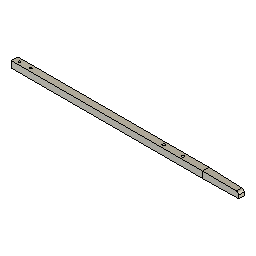
Assembly (Autodesk Fusion 360 archive; units mm, degrees)
design "Solid fuselage"
Autodesk Fusion 360 part; units mm, degrees
sketch "Profile" plane through (0, 0, 0) normal (1, 0, 0) x (0, 1, 0)
  line L0 (10, -10) -> (-10, -10)
  line L1 (-10, -10) -> (-10, 10)
  line L2 (-10, 10) -> (10, 10)
  line L3 (10, 10) -> (10, -10)
  line L4 (10, -10) -> (-10, 10) construction
  line L5 (-10, -10) -> (10, 10) construction
  dimension "d1" = 20
  dimension "d2" = 20
  constraint horizontal L0
  constraint perpendicular L0 L1
  constraint parallel L0 L2
  constraint parallel L1 L3
  constraint coincident L4 origin
  constraint coincident L5 origin
  measures "d1" distance of L0.end L1.end
  measures "d2" distance of L1.end L2.end
extrude "Extrude1" add sketch "Profile" along normal mid plane 700 makes body 1
sketch "Bottom" plane through (0, 0, -10) normal (0, 0, -1) x (1, 0, 0)
  line L0 (-350, -10) -> (350, -10)
  line L1 (350, -10) -> (350, 10)
  line L2 (350, 10) -> (-350, 10)
  line L3 (-350, 10) -> (-350, -10)
  line L4 (350, 0) -> (-28.4363, 0) construction
  circle A0 centre (245, 0) radius 3
  circle A1 centre (290, 0) radius 3
  circle A2 centre (335, 0) radius 3
  circle A3 centre (170, 0) radius 4
  circle A4 centre (110, 0) radius 4
  dimension "d5" = 6
  dimension "d6" = 15
  dimension "d7" = 45
  dimension "d8" = 45
  dimension "d35" = 8
  dimension "d36" = 8
  dimension "d37" = 60
  dimension "d38" = 180
  constraint midpoint L1 L4.start
  constraint perpendicular L1 L4
  constraint coincident L4 A0.centre
  constraint coincident L4 A2.centre
  constraint equal A1 A2
  constraint equal A0 A2
  constraint coincident L4 A1.centre
  constraint coincident L4 A3.centre
  constraint coincident L4 A4.centre
  measures "d5" diameter of A2
  measures "d6" distance of L1 A2.centre
  measures "d7" distance of A1.centre A2.centre
  measures "d8" distance of A0.centre A1.centre
  measures "d35" diameter of A3
  measures "d36" diameter of A4
  measures "d37" distance of A3.centre A4.centre
  measures "d38" distance of L1 A3.centre
sketch "Draft B" plane through (0, 0, -10) normal (0, 0, -1) x (1, 0, 0)
  line L0 (-350, -10) -> (350, -10)
  line L1 (350, -10) -> (350, 10)
  line L2 (350, 10) -> (-350, 10)
  line L3 (-350, 10) -> (-350, -10)
  line L4 (240, 10) -> (350, 8.25)
  line L5 (1.75, 0) -> (22.5, 0)
  line L6 (240, -10) -> (350, -8.25)
  line L7 (350, 0) -> (-28.4363, 0)
  line L8 (350, 8.25) -> (350, -8.25)
  dimension "d13" = 110
  dimension "d77" = 16.5
  constraint coincident L2 L4.start
  constraint coincident L1 L4.end
  constraint symmetric L4.start L5 L6.start
  constraint symmetric L4.end L5 L6.end
  constraint vertical L8
  constraint midpoint L7.start L8
  constraint coincident L4.end L8.start
  measures "d13" distance of L1.end L4.start
  measures "d77" distance of L6.end L4.end
sketch "Draft S" plane through (0, -10, 0) normal (0, -1, 0) x (1, 0, 0)
  line L0 (-350, -10) -> (350, -10)
  line L1 (350, -10) -> (350, 10)
  line L2 (350, 10) -> (-350, 10)
  line L3 (-350, 10) -> (-350, -10)
  line L4 (240, 10) -> (350, 7)
  line L5 (1.75, 0) -> (22.5, 0) construction
  line L6 (350, -10) -> (350, 7)
  dimension "d15" = 110
  dimension "d78" = 17
  constraint coincident L2 L4.start
  constraint coincident L1 L4.end
  constraint coincident L0.end L1.start
  constraint parallel L1 L6
  measures "d15" distance of L1.end L4.start
  measures "d78" distance of L4.end L0.end
extrude "Extrude2" cut sketch "Draft S" against normal through all contours L1 L2 L4 bodies 1
extrude "Extrude3" cut sketch "Draft B" against normal through all contours L0 L1 L6 | L1 L2 L4 bodies 1
sketch "Rear Wing" plane through (0, 0, 10) normal (0, 0, 1) x (-1, 0, 0)
  line L0 (-240, 10) -> (-240, -10)
  line L1 (-240, -10) -> (350, -10)
  line L2 (350, -10) -> (350, 10)
  line L3 (350, 10) -> (-240, 10)
  line L4 (350, 0) -> (250, 0) construction
  circle A0 centre (300, 0) radius 3
  circle A1 centre (335, 0) radius 3
  dimension "d20" = 6
  dimension "d21" = 15
  dimension "d22" = 35
  constraint perpendicular L2 L4
  constraint midpoint L4 A0.centre
  constraint coincident L4 A1.centre
  constraint equal A0 A1
  constraint coincident L2 L4.start
  measures "d20" diameter of A0
  measures "d21" distance of L2 A1.centre
  measures "d22" distance of A0.centre A1.centre
hole "Hole1" at (335, 0, -10) at (290, 0, -10) at (245, 0, -10) direction (0, 0, 1) diameter 6 depth 14.5 tip angle 118 bodies 1
hole "Hole4" at (170, 0, -10) at (110, 0, -10) direction (0, 0, 1) diameter 8 depth 60 tip angle 118 counterbore diameter 13 counterbore depth 9 bodies 1
hole "Hole3" at (-300, 0, 10) at (-335, 0, 10) direction (0, 0, -1) diameter 6 depth 15 tip angle 118 bodies 1
ref_plane "WorkPlane1" through (215, 0, 0) normal (1, 0, 0) x (0, 1, 0)
fillet "Fillet2" radius 7.5 1 edges at (350, 0, 7) on bodies 1
copy_body "Body->Comp1" bodies 1 removing the originals makes body 2 in component "Component"
equation "d1 = size"
equation "d2 = d1"
equation "d13 = todraft"
equation "d15 = todraft"
equation "draft = 2 mm"
equation "d36 = d35"
equation "d38 = mast"
equation "todraft = 110 mm"
equation "size = 20 mm"
equation "mast = 180 mm"
equation "d52 = d53"
equation "d53 = 24 mm"
